Autodesk Fusion 360 part; units mm, degrees
(part 13 of 18)
  line L9909 (187.203, -152.492) -> (187.673, -152.838)
  line L9910 (135.949, -198.554) -> (136.521, -198.435)
  line L9911 (78.42, -213.805) -> (77.9903, -214.201)
  line L9912 (69.6987, -215.983) -> (70.2761, -216.122)
  line L9913 (67.7724, -199.389) -> (68.2951, -199.128)
  line L9914 (174.108, -155.66) -> (174.402, -155.154)
  line L9915 (135.386, -198.709) -> (135.949, -198.554)
  line L9916 (63.1589, -205.81) -> (63.2769, -205.237)
  line L9917 (81.1268, -207.35) -> (81.1251, -207.524)
  line L9918 (173.035, -159.571) -> (173.078, -158.988)
  line L9919 (173.277, -157.837) -> (173.432, -157.274)
  line L9920 (144.823, -213.382) -> (144.42, -213.805)
  line L9921 (142.711, -199.576) -> (143.203, -199.892)
  line L9922 (66.7829, -200.01) -> (67.2676, -199.684)
  line L9923 (81.0514, -206.184) -> (81.1079, -206.766)
  line L9924 (190.922, -161.862) -> (190.781, -162.429)
  line L9925 (147.027, -208.688) -> (146.922, -209.262)
  line L9926 (68.8336, -198.901) -> (69.3856, -198.709)
  line L9927 (190.602, -162.986) -> (190.389, -163.53)
  line L9928 (81.0121, -206.757) -> (80.9531, -206.166)
  line L9929 (78.8234, -213.382) -> (78.42, -213.805)
  line L9930 (186.561, -167.811) -> (186.044, -168.084)
  line L9931 (79.1986, -212.934) -> (78.8234, -213.382)
  line L9932 (145.199, -212.934) -> (144.823, -213.382)
  line L9933 (85.3443, -157.966) -> (85.2321, -158.549)
  line L9934 (182.85, -150.933) -> (183.43, -151.002)
  line L9935 (184.404, -168.696) -> (183.835, -168.828)
  line L9936 (69.2202, -215.937) -> (68.672, -215.735)
  line L9937 (177.268, -152.284) -> (177.772, -151.989)
  line L9938 (63.495, -204.792) -> (63.3443, -205.366)
  line L9939 (63.0612, -208.139) -> (63.0291, -207.555)
  line L9940 (63.9741, -211.163) -> (64.2446, -211.691)
  line L9941 (188.543, -153.618) -> (188.938, -154.049)
  line L9942 (132.32, -200.367) -> (132.783, -200.01)
  line L9943 (173.061, -160.739) -> (173.029, -160.155)
  line L9944 (79.6409, -202.381) -> (79.9457, -202.88)
  line L9945 (189.199, -165.534) -> (188.823, -165.982)
  line L9946 (65.9695, -200.801) -> (65.5489, -201.22)
  line L9947 (144.938, -201.449) -> (145.304, -201.904)
  line L9948 (69.5484, -198.759) -> (68.9847, -198.946)
  line L9949 (90.9847, -151.546) -> (90.4345, -151.769)
  line L9950 (63.541, -210.058) -> (63.7392, -210.617)
  line L9951 (67.5183, -215.058) -> (68.0392, -215.343)
  line L9952 (133.772, -199.389) -> (134.295, -199.128)
  line L9953 (63.7392, -210.617) -> (63.9741, -211.163)
  line L9954 (131.084, -201.606) -> (131.469, -201.166)
  line L9955 (187.99, -166.801) -> (187.536, -167.168)
  line L9956 (78.0223, -214.047) -> (78.453, -213.638)
  line L9957 (78.8557, -213.201) -> (79.2286, -212.739)
  line L9958 (179.78, -168.704) -> (179.22, -168.537)
  line L9959 (69.1318, -215.807) -> (69.6987, -215.983)
  line L9960 (173.562, -163.016) -> (173.382, -162.46)
  line L9961 (77.5654, -214.426) -> (78.0223, -214.047)
  line L9962 (76.4456, -199.533) -> (75.9179, -199.261)
  line L9963 (71.4521, -216.283) -> (72.0455, -216.305)
  line L9964 (63.2578, -208.905) -> (63.3803, -209.486)
  line L9965 (102.827, -157.638) -> (102.957, -158.208)
  line L9966 (97.1275, -151.43) -> (97.671, -151.644)
  line L9967 (100.121, -153.214) -> (100.543, -153.618)
  line L9968 (103.051, -158.784) -> (103.108, -159.366)
  line L9969 (98.7108, -152.176) -> (99.2028, -152.492)
  line L9970 (96.0047, -151.108) -> (96.5713, -151.251)
  line L9971 (103.127, -159.95) -> (103.125, -160.124)
  line L9972 (101.641, -154.981) -> (101.946, -155.48)
  line L9973 (101.946, -155.48) -> (102.218, -155.997)
  line L9974 (102.957, -158.208) -> (103.051, -158.784)
  line L9975 (103.108, -159.366) -> (103.127, -159.95)
  line L9976 (97.671, -151.644) -> (98.1995, -151.894)
  line L9977 (96.5713, -151.251) -> (97.1275, -151.43)
  line L9978 (100.543, -153.618) -> (100.938, -154.049)
  line L9979 (102.218, -155.997) -> (102.456, -156.531)
  line L9980 (103.095, -160.707) -> (103.027, -161.288)
  line L9981 (102.456, -156.531) -> (102.659, -157.078)
  line L9982 (101.304, -154.504) -> (101.641, -154.981)
  line L9983 (99.2028, -152.492) -> (99.6734, -152.838)
  line L9984 (103.125, -160.124) -> (103.095, -160.707)
  line L9985 (98.1995, -151.894) -> (98.7108, -152.176)
  line L9986 (102.659, -157.078) -> (102.827, -157.638)
  line L9987 (100.938, -154.049) -> (101.304, -154.504)
  line L9988 (99.6734, -152.838) -> (100.121, -153.214)
  line L9989 (146.153, -140.119) -> (146.391, -139.576)
  line L9990 (74.4039, -144.996) -> (73.8346, -145.128)
  line L9991 (22.539, -143.287) -> (23.0175, -143.639)
  line L9992 (63.1297, -136.625) -> (63.1742, -137.217)
  line L9993 (20.5495, -141.101) -> (20.8876, -141.589)
  line L9994 (36.7806, -138.729) -> (36.6024, -139.286)
  line L9995 (63.9088, -132.579) -> (63.6834, -133.129)
  line L9996 (23.1214, -143.823) -> (22.643, -143.487)
  line L9997 (76.1995, -128.194) -> (76.7108, -128.476)
  line L9998 (139.816, -145.034) -> (140.395, -144.9)
  line L9999 (79.5441, -141.363) -> (79.1986, -141.834)
  line L10000 (81.0318, -136.25) -> (81.0121, -135.657)
  line L10001 (87.0836, -154.206) -> (87.4688, -153.766)
  line L10002 (23.2676, -128.584) -> (23.7724, -128.289)
  line L10003 (30.3945, -144.9) -> (30.9627, -144.727)
  line L10004 (22.3203, -129.267) -> (22.7829, -128.91)
  line L10005 (37.0514, -135.084) -> (37.1079, -135.666)
  line L10006 (79.8006, -131.718) -> (79.4833, -131.217)
  line L10007 (75.671, -127.944) -> (76.1995, -128.194)
  line L10008 (35.3045, -130.804) -> (35.6409, -131.281)
  line L10009 (74.8143, -127.724) -> (74.2432, -127.561)
  line L10010 (63.0291, -136.455) -> (63.0332, -136.031)
  line L10011 (34.0223, -142.947) -> (34.453, -142.538)
  line L10012 (63.495, -133.692) -> (63.3443, -134.266)
  line L10013 (74.5713, -127.551) -> (75.1275, -127.73)
  line L10014 (140.963, -144.727) -> (141.518, -144.517)
  line L10015 (74.9627, -144.727) -> (75.5182, -144.517)
  line L10016 (33.6734, -129.138) -> (34.1207, -129.514)
  line L10017 (137.452, -145.183) -> (138.046, -145.205)
  line L10018 (29.2581, -145.223) -> (28.6766, -145.28)
  line L10019 (63.0332, -136.031) -> (63.0347, -135.871)
  line L10020 (36.3914, -139.576) -> (36.5935, -139.017)
  line L10021 (19.0612, -137.039) -> (19.0291, -136.455)
  line L10022 (85.1589, -158.41) -> (85.2769, -157.837)
  line L10023 (78.7525, -130.281) -> (78.3423, -129.852)
  line L10024 (86.7274, -154.669) -> (87.0836, -154.206)
  line L10025 (30.5713, -127.551) -> (31.1275, -127.73)
  line L10026 (25.1318, -144.707) -> (25.6987, -144.883)
  line L10027 (131.657, -142.493) -> (132.085, -142.905)
  line L10028 (68.672, -144.635) -> (68.138, -144.398)
  line L10029 (80.3914, -139.576) -> (80.5935, -139.017)
  line L10030 (72.0926, -145.3) -> (71.5085, -145.282)
  line L10031 (37.1251, -136.424) -> (37.0951, -137.007)
  line L10032 (80.8551, -134.48) -> (80.7185, -133.902)
  line L10033 (79.1334, -130.737) -> (78.7525, -130.281)
  line L10034 (26.5208, -127.335) -> (27.0994, -127.253)
  line L10035 (141.918, -128.161) -> (141.373, -127.924)
  line L10036 (73.6626, -127.437) -> (73.075, -127.351)
  line L10037 (69.5484, -127.659) -> (68.9847, -127.846)
  line L10038 (143.565, -143.326) -> (144.022, -142.947)
  line L10039 (65.9695, -153.401) -> (65.5489, -153.82)
  line L10040 (63.1245, -159.731) -> (63.1297, -160.325)
  line L10041 (136.123, -127.511) -> (135.548, -127.659)
  line L10042 (22.0847, -142.905) -> (22.539, -143.287)
  line L10043 (80.5935, -139.017) -> (80.7582, -138.447)
  line L10044 (79.8585, -140.87) -> (79.5441, -141.363)
  line L10045 (78.1207, -129.514) -> (78.5428, -129.918)
  line L10046 (129.683, -133.129) -> (129.495, -133.692)
  line L10047 (20.402, -131.454) -> (20.7274, -130.969)
  line L10048 (63.1587, -135.438) -> (63.1245, -136.031)
  line L10049 (64.5495, -141.101) -> (64.8876, -141.589)
  line L10050 (23.0175, -143.639) -> (23.5183, -143.958)
  line L10051 (64.9746, -141.859) -> (64.6274, -141.389)
  line L10052 (147.032, -136.25) -> (147.012, -135.657)
  line L10053 (25.2202, -144.837) -> (24.672, -144.635)
  line L10054 (145.801, -131.718) -> (145.483, -131.217)
  line L10055 (66.8893, -128.951) -> (66.417, -129.31)
  line L10056 (130.795, -131.037) -> (130.466, -131.531)
  line L10057 (24.8336, -127.801) -> (25.3856, -127.609)
  line L10058 (140.243, -127.561) -> (139.663, -127.437)
  line L10059 (34.8557, -142.101) -> (35.2286, -141.639)
  line L10060 (81.1268, -136.25) -> (81.1251, -136.424)
  line L10061 (77.9903, -143.101) -> (77.5358, -143.468)
  line L10062 (77.2028, -128.792) -> (77.6734, -129.138)
  line L10063 (130.17, -132.046) -> (129.909, -132.579)
  line L10064 (63.6834, -133.129) -> (63.495, -133.692)
  line L10065 (67.1214, -143.823) -> (66.643, -143.487)
  line L10066 (30.9634, -144.827) -> (30.4039, -144.996)
  line L10067 (136.276, -145.022) -> (136.861, -145.122)
  line L10068 (69.7803, -145.004) -> (69.2202, -144.837)
  line L10069 (19.3803, -138.386) -> (19.541, -138.958)
  line L10070 (66.0847, -142.905) -> (66.539, -143.287)
  line L10071 (19.3817, -138.76) -> (19.2379, -138.193)
  line L10072 (65.8816, -129.653) -> (66.3203, -129.267)
  line L10073 (72.0455, -145.205) -> (72.6391, -145.187)
  line L10074 (33.2028, -128.792) -> (33.6734, -129.138)
  line L10075 (75.9179, -151.861) -> (75.3734, -151.624)
  line L10076 (146.758, -138.447) -> (146.885, -137.867)
  line L10077 (81.0121, -135.657) -> (80.9531, -135.066)
  line L10078 (135.699, -144.883) -> (136.276, -145.022)
  line L10079 (31.5109, -144.623) -> (30.9634, -144.827)
  line L10080 (134.434, -128.069) -> (133.9, -128.329)
  line L10081 (63.1589, -134.71) -> (63.2769, -134.137)
  line L10082 (93.682, -150.909) -> (94.2663, -150.902)
  line L10083 (87.8816, -153.353) -> (88.3203, -152.967)
  line L10084 (20.0276, -140.387) -> (19.7774, -139.859)
  line L10085 (72.2663, -127.202) -> (72.8498, -127.233)
  line L10086 (133.518, -143.958) -> (134.039, -144.243)
  line L10087 (80.9575, -134.508) -> (81.0514, -135.084)
  line L10088 (36.8847, -137.867) -> (36.9725, -137.279)
  line L10089 (71.8893, -150.997) -> (71.2963, -151.029)
  line L10090 (143.084, -143.674) -> (143.565, -143.326)
  line L10091 (20.8876, -141.589) -> (21.2572, -142.054)
  line L10092 (35.57, -141.153) -> (35.8785, -140.646)
  line L10093 (73.8346, -145.128) -> (73.2581, -145.223)
  line L10094 (63.078, -135.288) -> (63.1589, -134.71)
  line L10095 (64.17, -132.046) -> (63.9088, -132.579)
  line L10096 (63.232, -134.849) -> (63.1587, -135.438)
  line L10097 (137.889, -127.297) -> (137.296, -127.329)
  line L10098 (147.012, -135.657) -> (146.953, -135.066)
  line L10099 (68.2951, -128.028) -> (68.8336, -127.801)
  line L10100 (25.9488, -127.454) -> (26.5208, -127.335)
  line L10101 (129.159, -135.438) -> (129.124, -136.031)
  line L10102 (70.5208, -127.335) -> (71.0994, -127.253)
  line L10103 (20.6274, -141.389) -> (20.3113, -140.898)
  line L10104 (19.5618, -139.316) -> (19.3817, -138.76)
  line L10105 (173.541, -162.658) -> (173.739, -163.217)
  line L10106 (65.157, -154.266) -> (64.7955, -154.737)
  line L10107 (28.0926, -145.3) -> (27.5085, -145.282)
  line L10108 (80.7185, -133.902) -> (80.5439, -133.335)
  line L10109 (72.8498, -127.233) -> (73.4301, -127.302)
  line L10110 (135.132, -144.707) -> (135.699, -144.883)
  line L10111 (85.6222, -156.722) -> (85.8482, -156.183)
  line L10112 (144.453, -142.538) -> (144.856, -142.101)
  line L10113 (89.7724, -151.989) -> (90.2951, -151.728)
  line L10114 (76.7108, -128.476) -> (77.2028, -128.792)
  line L10115 (134.039, -144.243) -> (134.578, -144.493)
  line L10116 (78.3423, -153.552) -> (77.9045, -153.151)
  line L10117 (36.4559, -132.831) -> (36.6591, -133.378)
  line L10118 (79.8006, -155.418) -> (79.4833, -154.917)
  line L10119 (77.4411, -129.079) -> (76.954, -128.74)
  line L10120 (88.3203, -152.967) -> (88.7829, -152.61)
  line L10121 (146.594, -139.017) -> (146.758, -138.447)
  line L10122 (32.0441, -144.384) -> (31.5109, -144.623)
  line L10123 (26.2761, -145.022) -> (26.8615, -145.122)
  line L10124 (34.42, -142.705) -> (33.9903, -143.101)
  line L10125 (80.6591, -133.378) -> (80.8266, -133.938)
  line L10126 (76.0441, -144.384) -> (75.5109, -144.623)
  line L10127 (95.4301, -151.002) -> (96.0047, -151.108)
  line L10128 (64.6274, -141.389) -> (64.3113, -140.898)
  line L10129 (29.8346, -145.128) -> (29.2581, -145.223)
  line L10130 (19.2578, -137.805) -> (19.3803, -138.386)
  line L10131 (78.7525, -153.981) -> (78.3423, -153.552)
  line L10132 (80.9531, -135.066) -> (80.8551, -134.48)
  line L10133 (29.2302, -145.13) -> (29.8162, -145.034)
  line L10134 (24.5778, -144.493) -> (25.1318, -144.707)
  line L10135 (65.7561, -142.727) -> (65.3513, -142.306)
  line L10136 (64.3113, -140.898) -> (64.0276, -140.387)
  line L10137 (69.5484, -151.359) -> (68.9847, -151.546)
  line L10138 (33.0587, -143.805) -> (32.5607, -144.111)
  line L10139 (64.7274, -130.969) -> (65.0836, -130.506)
  line L10140 (73.075, -151.051) -> (72.483, -151.004)
  line L10141 (146.972, -137.279) -> (147.021, -136.687)
  line L10142 (63.3817, -138.76) -> (63.2379, -138.193)
  line L10143 (86.1085, -155.66) -> (86.402, -155.154)
  line L10144 (91.3856, -151.309) -> (91.9488, -151.154)
  line L10145 (81.1251, -136.424) -> (81.0951, -137.007)
  line L10146 (70.7068, -127.4) -> (70.1233, -127.511)
  line L10147 (69.3856, -127.609) -> (69.9488, -127.454)
  line L10148 (36.6591, -133.378) -> (36.8266, -133.938)
  line L10149 (63.0612, -137.039) -> (63.0291, -136.455)
  line L10150 (34.453, -142.538) -> (34.8557, -142.101)
  line L10151 (21.7561, -142.727) -> (21.3513, -142.306)
  line L10152 (80.5439, -133.335) -> (80.3321, -132.78)
  line L10153 (141.518, -144.517) -> (142.059, -144.271)
  line L10154 (72.483, -127.304) -> (71.8893, -127.297)
  line L10155 (63.2769, -134.137) -> (63.4315, -133.574)
  line L10156 (78.42, -142.705) -> (77.9903, -143.101)
  line L10157 (65.157, -130.566) -> (64.7955, -131.037)
  line L10158 (63.6222, -133.022) -> (63.8482, -132.483)
  line L10159 (78.453, -142.538) -> (78.8557, -142.101)
  line L10160 (68.4345, -151.769) -> (67.9003, -152.029)
  line L10161 (63.541, -138.958) -> (63.7392, -139.517)
  line L10162 (77.6734, -129.138) -> (78.1207, -129.514)
  line L10163 (68.9847, -151.546) -> (68.4345, -151.769)
  line L10164 (132.539, -143.287) -> (133.018, -143.639)
  line L10165 (138.639, -145.187) -> (139.23, -145.13)
  line L10166 (74.2432, -151.261) -> (73.6626, -151.137)
  line L10167 (21.0836, -130.506) -> (21.4688, -130.066)
  line L10168 (22.7829, -128.91) -> (23.2676, -128.584)
  line L10169 (64.2446, -140.591) -> (64.5495, -141.101)
  line L10170 (80.7806, -138.729) -> (80.6024, -139.286)
  line L10171 (81.0514, -135.084) -> (81.1079, -135.666)
  line L10172 (137.296, -127.329) -> (136.707, -127.4)
  line L10173 (146.332, -132.78) -> (146.084, -132.24)
  line L10174 (70.1233, -151.211) -> (69.5484, -151.359)
  line L10175 (78.3423, -129.852) -> (77.9045, -129.451)
  line L10176 (142.581, -143.99) -> (143.084, -143.674)
  line L10177 (68.5778, -144.493) -> (69.1318, -144.707)
  line L10178 (70.7068, -151.1) -> (70.1233, -151.211)
  line L10179 (80.3887, -139.83) -> (80.1404, -140.359)
  line L10180 (36.5935, -139.017) -> (36.7582, -138.447)
  line L10181 (19.0347, -135.871) -> (19.078, -135.288)
  line L10182 (32.5607, -144.111) -> (32.0441, -144.384)
  line L10183 (80.2178, -132.297) -> (80.4559, -132.831)
  line L10184 (68.0392, -144.243) -> (68.5778, -144.493)
  line L10185 (25.3856, -127.609) -> (25.9488, -127.454)
  line L10186 (19.2379, -138.193) -> (19.1309, -137.619)
  line L10187 (68.8336, -127.801) -> (69.3856, -127.609)
  line L10188 (85.8482, -156.183) -> (86.1085, -155.66)
  line L10189 (63.0347, -135.871) -> (63.078, -135.288)
  line L10190 (21.4688, -130.066) -> (21.8816, -129.653)
  line L10191 (74.3945, -144.9) -> (74.9627, -144.727)
  line L10192 (142.059, -144.271) -> (142.581, -143.99)
  line L10193 (70.1233, -127.511) -> (69.5484, -127.659)
  line L10194 (75.1275, -127.73) -> (75.671, -127.944)
  line L10195 (19.2769, -134.137) -> (19.4315, -133.574)
  line L10196 (145.879, -140.646) -> (146.153, -140.119)
  line L10197 (63.1587, -159.138) -> (63.1245, -159.731)
  line L10198 (64.17, -155.746) -> (63.9088, -156.279)
  line L10199 (20.3113, -140.898) -> (20.0276, -140.387)
  line L10200 (64.402, -131.454) -> (64.7274, -130.969)
  line L10201 (79.6409, -131.281) -> (79.9457, -131.78)
  line L10202 (80.1404, -140.359) -> (79.8585, -140.87)
  line L10203 (145.133, -130.737) -> (144.753, -130.281)
  line L10204 (78.9379, -130.349) -> (79.3045, -130.804)
  line L10205 (138.046, -145.205) -> (138.639, -145.187)
  line L10206 (67.9003, -128.329) -> (67.3845, -128.623)
  line L10207 (37.0274, -137.588) -> (36.9224, -138.162)
  line L10208 (80.1527, -140.119) -> (80.3914, -139.576)
  line L10209 (73.6626, -151.137) -> (73.075, -151.051)
  line L10210 (73.2302, -145.13) -> (73.8162, -145.034)
  line L10211 (131.97, -129.701) -> (131.549, -130.12)
  line L10212 (81.1079, -135.666) -> (81.1268, -136.25)
  line L10213 (80.9224, -138.162) -> (80.7806, -138.729)
  line L10214 (23.5183, -143.958) -> (24.0392, -144.243)
  line L10215 (19.9741, -140.063) -> (20.2446, -140.591)
  line L10216 (65.6569, -142.493) -> (66.0847, -142.905)
  line L10217 (144.342, -129.852) -> (143.904, -129.451)
  line L10218 (64.1085, -131.96) -> (64.402, -131.454)
  line L10219 (71.682, -127.209) -> (72.2663, -127.202)
  line L10220 (132.417, -129.31) -> (131.97, -129.701)
  line L10221 (67.9003, -152.029) -> (67.3845, -152.323)
  line L10222 (23.6204, -144.127) -> (23.1214, -143.823)
  line L10223 (26.8615, -145.122) -> (27.4521, -145.183)
  line L10224 (87.4688, -153.766) -> (87.8816, -153.353)
  line L10225 (80.084, -132.24) -> (79.8006, -131.718)
  line L10226 (73.075, -127.351) -> (72.483, -127.304)
  line L10227 (67.7724, -128.289) -> (68.2951, -128.028)
  line L10228 (31.1275, -127.73) -> (31.671, -127.944)
  line L10229 (64.466, -155.231) -> (64.17, -155.746)
  line L10230 (80.7582, -138.447) -> (80.8847, -137.867)
  line L10231 (65.3513, -142.306) -> (64.9746, -141.859)
  line L10232 (63.5618, -139.316) -> (63.3817, -138.76)
  line L10233 (20.7274, -130.969) -> (21.0836, -130.506)
  line L10234 (20.9746, -141.859) -> (20.6274, -141.389)
  line L10235 (146.885, -137.867) -> (146.972, -137.279)
  line L10236 (74.2432, -127.561) -> (73.6626, -127.437)
  line L10237 (63.8482, -132.483) -> (64.1085, -131.96)
  line L10238 (142.954, -128.74) -> (142.446, -128.433)
  line L10239 (35.1986, -141.834) -> (34.8234, -142.282)
  line L10240 (36.3887, -139.83) -> (36.1404, -140.359)
  line L10241 (133.018, -143.639) -> (133.518, -143.958)
  line L10242 (75.9179, -128.161) -> (75.3734, -127.924)
  line L10243 (28.6391, -145.187) -> (29.2302, -145.13)
  line L10244 (80.4559, -132.831) -> (80.6591, -133.378)
  line L10245 (63.9088, -156.279) -> (63.6834, -156.829)
  line L10246 (146.855, -134.48) -> (146.719, -133.902)
  line L10247 (146.953, -135.066) -> (146.855, -134.48)
  line L10248 (79.1986, -141.834) -> (78.8234, -142.282)
  line L10249 (24.2951, -128.028) -> (24.8336, -127.801)
  line L10250 (144.753, -130.281) -> (144.342, -129.852)
  line L10251 (23.7724, -128.289) -> (24.2951, -128.028)
  line L10252 (78.0223, -142.947) -> (78.453, -142.538)
  line L10253 (146.544, -133.335) -> (146.332, -132.78)
  line L10254 (19.7774, -139.859) -> (19.5618, -139.316)
  line L10255 (85.078, -158.988) -> (85.1589, -158.41)
  line L10256 (78.8234, -142.282) -> (78.42, -142.705)
  line L10257 (19.7392, -139.517) -> (19.9741, -140.063)
  line L10258 (26.9269, -145.227) -> (26.35, -145.134)
  line L10259 (80.8266, -133.938) -> (80.9575, -134.508)
  line L10260 (66.3203, -129.267) -> (66.7829, -128.91)
  line L10261 (133.385, -128.623) -> (132.889, -128.951)
  line L10262 (31.671, -127.944) -> (32.1995, -128.194)
  line L10263 (79.2286, -141.639) -> (79.57, -141.153)
  line L10264 (19.0332, -136.031) -> (19.0347, -135.871)
  line L10265 (71.2963, -151.029) -> (70.7068, -151.1)
  line L10266 (88.7829, -152.61) -> (89.2676, -152.284)
  line L10267 (37.1079, -135.666) -> (37.1268, -136.25)
  line L10268 (19.1742, -137.217) -> (19.2578, -137.805)
  line L10269 (69.1318, -144.707) -> (69.6987, -144.883)
  line L10270 (80.3321, -132.78) -> (80.084, -132.24)
  line L10271 (79.4833, -154.917) -> (79.1334, -154.437)
  line L10272 (75.5109, -144.623) -> (74.9634, -144.827)
  line L10273 (32.0585, -144.271) -> (32.5813, -143.99)
  line L10274 (91.9488, -151.154) -> (92.5208, -151.035)
  line L10275 (131.257, -142.054) -> (131.657, -142.493)
  line L10276 (75.3734, -127.924) -> (74.8143, -127.724)
  line L10277 (68.4345, -128.069) -> (67.9003, -128.329)
  line L10278 (19.1589, -134.71) -> (19.2769, -134.137)
  line L10279 (78.8557, -142.101) -> (79.2286, -141.639)
  line L10280 (19.1309, -137.619) -> (19.0612, -137.039)
  line L10281 (76.5813, -143.99) -> (77.0844, -143.674)
  line L10282 (66.417, -153.01) -> (65.9695, -153.401)
  line L10283 (85.2769, -157.837) -> (85.4315, -157.274)
  line L10284 (20.2446, -140.591) -> (20.5495, -141.101)
  line L10285 (80.6024, -139.286) -> (80.3887, -139.83)
  line L10286 (90.2951, -151.728) -> (90.8336, -151.501)
  line L10287 (93.0994, -150.953) -> (93.682, -150.909)
  line L10288 (21.6569, -142.493) -> (22.0847, -142.905)
  line L10289 (35.6409, -131.281) -> (35.9457, -131.78)
  line L10290 (21.2572, -142.054) -> (21.6569, -142.493)
  line L10291 (79.57, -141.153) -> (79.8785, -140.646)
  line L10292 (63.1309, -137.619) -> (63.0612, -137.039)
  line L10293 (66.7829, -128.91) -> (67.2676, -128.584)
  line L10294 (67.3845, -128.623) -> (66.8893, -128.951)
  line L10295 (68.9847, -127.846) -> (68.4345, -128.069)
  line L10296 (66.417, -129.31) -> (65.9695, -129.701)
  line L10297 (36.8266, -133.938) -> (36.9575, -134.508)
  line L10298 (71.2963, -127.329) -> (70.7068, -127.4)
  line L10299 (71.5085, -145.282) -> (70.9269, -145.227)
  line L10300 (78.5428, -129.918) -> (78.9379, -130.349)
  line L10301 (63.1742, -137.217) -> (63.2578, -137.805)
  line L10302 (89.2676, -152.284) -> (89.7724, -151.989)
  line L10303 (145.229, -141.639) -> (145.57, -141.153)
  line L10304 (81.0274, -137.588) -> (80.9224, -138.162)
  line L10305 (64.0276, -140.387) -> (63.7774, -139.859)
  line L10306 (67.2676, -128.584) -> (67.7724, -128.289)
  line L10307 (79.3045, -130.804) -> (79.6409, -131.281)
  line L10308 (35.9457, -131.78) -> (36.2178, -132.297)
  line L10309 (25.6987, -144.883) -> (26.2761, -145.022)
  line L10310 (139.075, -127.351) -> (138.483, -127.304)
  line L10311 (134.985, -127.846) -> (134.434, -128.069)
  line L10312 (35.8785, -140.646) -> (36.1527, -140.119)
  line L10313 (74.9634, -144.827) -> (74.4039, -144.996)
  line L10314 (36.6024, -139.286) -> (36.3887, -139.83)
  line L10315 (34.1207, -129.514) -> (34.5428, -129.918)
  line L10316 (66.643, -143.487) -> (66.1873, -143.121)
  line L10317 (80.8847, -137.867) -> (80.9725, -137.279)
  line L10318 (144.856, -142.101) -> (145.229, -141.639)
  line L10319 (63.495, -157.392) -> (63.3443, -157.966)
  line L10320 (79.4833, -131.217) -> (79.1334, -130.737)
  line L10321 (67.3845, -152.323) -> (66.8893, -152.651)
  line L10322 (63.7774, -139.859) -> (63.5618, -139.316)
  line L10323 (139.23, -145.13) -> (139.816, -145.034)
  line L10324 (81.0951, -137.007) -> (81.0274, -137.588)
  line L10325 (69.9488, -127.454) -> (70.5208, -127.335)
  line L10326 (37.0211, -136.687) -> (37.0318, -136.25)
  line L10327 (129.13, -136.625) -> (129.174, -137.217)
  line L10328 (27.5085, -145.282) -> (26.9269, -145.227)
  line L10329 (66.8893, -152.651) -> (66.417, -153.01)
  line L10330 (64.7955, -131.037) -> (64.466, -131.531)
  line L10331 (133.9, -128.329) -> (133.385, -128.623)
  line L10332 (37.1268, -136.25) -> (37.1251, -136.424)
  line L10333 (72.6391, -145.187) -> (73.2302, -145.13)
  line L10334 (86.402, -155.154) -> (86.7274, -154.669)
  line L10335 (76.954, -128.74) -> (76.4456, -128.433)
  line L10336 (146.391, -139.576) -> (146.594, -139.017)
  line L10337 (27.0994, -127.253) -> (27.682, -127.209)
  line L10338 (145.483, -131.217) -> (145.133, -130.737)
  line L10339 (30.4039, -144.996) -> (29.8346, -145.128)
  line L10340 (67.0175, -143.639) -> (67.5183, -143.958)
  line L10341 (79.9457, -131.78) -> (80.2178, -132.297)
  line L10342 (129.232, -134.849) -> (129.159, -135.438)
  line L10343 (63.2578, -137.805) -> (63.3803, -138.386)
  line L10344 (75.3734, -151.624) -> (74.8143, -151.424)
  line L10345 (33.0844, -143.674) -> (33.5654, -143.326)
  line L10346 (90.8336, -151.501) -> (91.3856, -151.309)
  line L10347 (63.2379, -138.193) -> (63.1309, -137.619)
  line L10348 (35.5441, -141.363) -> (35.1986, -141.834)
  line L10349 (79.8785, -140.646) -> (80.1527, -140.119)
  line L10350 (143.441, -129.079) -> (142.954, -128.74)
  line L10351 (33.5654, -143.326) -> (34.0223, -142.947)
  line L10352 (94.8498, -150.933) -> (95.4301, -151.002)
  line L10353 (63.7392, -139.517) -> (63.9741, -140.063)
  line L10354 (141.373, -127.924) -> (140.814, -127.724)
  line L10355 (131.157, -130.566) -> (130.795, -131.037)
  line L10356 (146.719, -133.902) -> (146.544, -133.335)
  line L10357 (32.7108, -128.476) -> (33.2028, -128.792)
  line L10358 (77.5654, -143.326) -> (78.0223, -142.947)
  line L10359 (31.5182, -144.517) -> (32.0585, -144.271)
  line L10360 (63.3443, -157.966) -> (63.232, -158.549)
  line L10361 (36.2178, -132.297) -> (36.4559, -132.831)
  line L10362 (64.7955, -154.737) -> (64.466, -155.231)
  line L10363 (36.9224, -138.162) -> (36.7806, -138.729)
  line L10364 (24.0392, -144.243) -> (24.5778, -144.493)
  line L10365 (64.466, -131.531) -> (64.17, -132.046)
  line L10366 (72.483, -151.004) -> (71.8893, -150.997)
  line L10367 (27.682, -127.209) -> (28.2663, -127.202)
  line L10368 (28.0455, -145.205) -> (28.6391, -145.187)
  line L10369 (34.5428, -129.918) -> (34.9379, -130.349)
  line L10370 (79.1334, -154.437) -> (78.7525, -153.981)
  line L10371 (28.2663, -127.202) -> (28.8498, -127.233)
  line L10372 (66.539, -143.287) -> (67.0175, -143.639)
  line L10373 (71.0994, -127.253) -> (71.682, -127.209)
  line L10374 (70.2761, -145.022) -> (70.8615, -145.122)
  line L10375 (69.2202, -144.837) -> (68.672, -144.635)
  line L10376 (63.6834, -156.829) -> (63.495, -157.392)
  line L10377 (70.35, -145.134) -> (69.7803, -145.004)
  line L10378 (81.0211, -136.687) -> (81.0318, -136.25)
  line L10379 (65.5489, -130.12) -> (65.157, -130.566)
  line L10380 (32.1995, -128.194) -> (32.7108, -128.476)
  line L10381 (30.0047, -127.408) -> (30.5713, -127.551)
  line L10382 (29.8162, -145.034) -> (30.3945, -144.9)
  line L10383 (66.1873, -143.121) -> (65.7561, -142.727)
  line L10384 (24.672, -144.635) -> (24.138, -144.398)
  line L10385 (33.9903, -143.101) -> (33.5358, -143.468)
  line L10386 (77.5358, -143.468) -> (77.0587, -143.805)
  line L10387 (130.466, -131.531) -> (130.17, -132.046)
  line L10388 (19.8482, -132.483) -> (20.1085, -131.96)
  line L10389 (63.232, -158.549) -> (63.1587, -159.138)
  line L10390 (85.4315, -157.274) -> (85.6222, -156.722)
  line L10391 (63.1245, -136.031) -> (63.1297, -136.625)
  line L10392 (134.578, -144.493) -> (135.132, -144.707)
  line L10393 (68.138, -144.398) -> (67.6204, -144.127)
  line L10394 (26.35, -145.134) -> (25.7803, -145.004)
  line L10395 (36.1527, -140.119) -> (36.3914, -139.576)
  line L10396 (129.124, -136.031) -> (129.13, -136.625)
  line L10397 (71.8893, -127.297) -> (71.2963, -127.329)
  line L10398 (34.9379, -130.349) -> (35.3045, -130.804)
  line L10399 (138.483, -127.304) -> (137.889, -127.297)
  line L10400 (33.5358, -143.468) -> (33.0587, -143.805)
  line L10401 (77.9045, -153.151) -> (77.4411, -152.779)
  line L10402 (36.9575, -134.508) -> (37.0514, -135.084)
  line L10403 (22.643, -143.487) -> (22.1873, -143.121)
  line L10404 (32.5813, -143.99) -> (33.0844, -143.674)
  line L10405 (20.1085, -131.96) -> (20.402, -131.454)
  line L10406 (19.078, -135.288) -> (19.1589, -134.71)
  line L10407 (24.138, -144.398) -> (23.6204, -144.127)
  line L10408 (77.0844, -143.674) -> (77.5654, -143.326)
  line L10409 (136.707, -127.4) -> (136.123, -127.511)
  line L10410 (19.541, -138.958) -> (19.7392, -139.517)
  line L10411 (63.3803, -138.386) -> (63.541, -138.958)
  line L10412 (76.954, -152.44) -> (76.4456, -152.133)
  line L10413 (76.5607, -144.111) -> (76.0441, -144.384)
  line L10414 (80.084, -155.94) -> (79.8006, -155.418)
  line L10415 (143.904, -129.451) -> (143.441, -129.079)
  line L10416 (140.814, -127.724) -> (140.243, -127.561)
  line L10417 (70.9269, -145.227) -> (70.35, -145.134)
  line L10418 (69.6987, -144.883) -> (70.2761, -145.022)
  line L10419 (71.4521, -145.183) -> (72.0455, -145.205)
  line L10420 (28.6766, -145.28) -> (28.0926, -145.3)
  line L10421 (76.0585, -144.271) -> (76.5813, -143.99)
  line L10422 (22.1873, -143.121) -> (21.7561, -142.727)
  line L10423 (28.8498, -127.233) -> (29.4301, -127.302)
  line L10424 (36.9725, -137.279) -> (37.0211, -136.687)
  line L10425 (132.889, -128.951) -> (132.417, -129.31)
  line L10426 (70.8615, -145.122) -> (71.4521, -145.183)
  line L10427 (136.861, -145.122) -> (137.452, -145.183)
  line L10428 (63.3443, -134.266) -> (63.232, -134.849)
  line L10429 (65.9695, -129.701) -> (65.5489, -130.12)
  line L10430 (146.084, -132.24) -> (145.801, -131.718)
  line L10431 (63.9741, -140.063) -> (64.2446, -140.591)
  line L10432 (92.5208, -151.035) -> (93.0994, -150.953)
  line L10433 (132.085, -142.905) -> (132.539, -143.287)
  line L10434 (65.5489, -153.82) -> (65.157, -154.266)
  line L10435 (135.548, -127.659) -> (134.985, -127.846)
  line L10436 (75.5182, -144.517) -> (76.0585, -144.271)
  line L10437 (131.549, -130.12) -> (131.157, -130.566)
  line L10438 (77.0587, -143.805) -> (76.5607, -144.111)
  line L10439 (27.4521, -145.183) -> (28.0455, -145.205)
  line L10440 (129.344, -134.266) -> (129.232, -134.849)
  line L10441 (76.4456, -152.133) -> (75.9179, -151.861)
  line L10442 (19.0291, -136.455) -> (19.0332, -136.031)
  line L10443 (25.7803, -145.004) -> (25.2202, -144.837)
  line L10444 (147.021, -136.687) -> (147.032, -136.25)
  line L10445 (76.4456, -128.433) -> (75.9179, -128.161)
  line L10446 (145.57, -141.153) -> (145.879, -140.646)
  line L10447 (67.5183, -143.958) -> (68.0392, -144.243)
  line L10448 (29.4301, -127.302) -> (30.0047, -127.408)
  line L10449 (74.0047, -127.408) -> (74.5713, -127.551)
  line L10450 (73.8162, -145.034) -> (74.3945, -144.9)
  line L10451 (129.495, -133.692) -> (129.344, -134.266)
  line L10452 (77.4411, -152.779) -> (76.954, -152.44)
  line L10453 (74.8143, -151.424) -> (74.2432, -151.261)
  line L10454 (73.2581, -145.223) -> (72.6766, -145.28)
  line L10455 (63.1297, -160.325) -> (63.1742, -160.917)
  line L10456 (30.9627, -144.727) -> (31.5182, -144.517)
  line L10457 (139.663, -127.437) -> (139.075, -127.351)
  line L10458 (65.4688, -130.066) -> (65.8816, -129.653)
  line L10459 (35.8585, -140.87) -> (35.5441, -141.363)
  line L10460 (37.0951, -137.007) -> (37.0274, -137.588)
  line L10461 (21.3513, -142.306) -> (20.9746, -141.859)
  line L10462 (63.4315, -133.574) -> (63.6222, -133.022)
  line L10463 (72.6766, -145.28) -> (72.0926, -145.3)
  line L10464 (34.8234, -142.282) -> (34.42, -142.705)
  line L10465 (65.0836, -130.506) -> (65.4688, -130.066)
  line L10466 (36.1404, -140.359) -> (35.8585, -140.87)
  line L10467 (19.4315, -133.574) -> (19.6222, -133.022)
  line L10468 (65.2572, -142.054) -> (65.6569, -142.493)
  line L10469 (64.8876, -141.589) -> (65.2572, -142.054)
  line L10470 (19.6222, -133.022) -> (19.8482, -132.483)
  line L10471 (73.4301, -127.302) -> (74.0047, -127.408)
  line L10472 (35.2286, -141.639) -> (35.57, -141.153)
  line L10473 (80.9725, -137.279) -> (81.0211, -136.687)
  line L10474 (21.8816, -129.653) -> (22.3203, -129.267)
  line L10475 (129.909, -132.579) -> (129.683, -133.129)
  line L10476 (94.2663, -150.902) -> (94.8498, -150.933)
  line L10477 (77.9045, -129.451) -> (77.4411, -129.079)
  line L10478 (67.6204, -144.127) -> (67.1214, -143.823)
  line L10479 (142.446, -128.433) -> (141.918, -128.161)
  line L10480 (140.395, -144.9) -> (140.963, -144.727)
  line L10481 (144.022, -142.947) -> (144.453, -142.538)
  line L10482 (36.7582, -138.447) -> (36.8847, -137.867)
  line L10483 (100.856, -165.801) -> (101.229, -165.339)
  line L10484 (85.9741, -163.763) -> (86.2446, -164.291)
  line L10485 (102.389, -163.53) -> (102.14, -164.059)
  line L10486 (86.6274, -165.089) -> (86.3113, -164.598)
  line L10487 (101.57, -164.853) -> (101.879, -164.346)
  line L10488 (92.2761, -168.722) -> (92.8615, -168.822)
  line L10489 (85.3803, -162.086) -> (85.541, -162.658)
  line L10490 (96.3945, -168.6) -> (96.9627, -168.427)
  line L10491 (97.5182, -168.217) -> (98.0585, -167.971)
  line L10492 (87.6569, -166.193) -> (88.0847, -166.605)
  line L10493 (95.8162, -168.734) -> (96.3945, -168.6)
  line L10494 (86.2446, -164.291) -> (86.5495, -164.801)
  line L10495 (101.879, -164.346) -> (102.153, -163.819)
  line L10496 (86.3113, -164.598) -> (86.0276, -164.087)
  line L10497 (86.0276, -164.087) -> (85.7774, -163.559)
  line L10498 (101.229, -165.339) -> (101.57, -164.853)
  line L10499 (101.544, -165.063) -> (101.199, -165.534)
  line L10500 (90.0392, -167.943) -> (90.5778, -168.193)
  line L10501 (88.0847, -166.605) -> (88.539, -166.987)
  line L10502 (85.5618, -163.016) -> (85.3817, -162.46)
  line L10503 (88.643, -167.187) -> (88.1873, -166.821)
  line L10504 (85.0332, -159.731) -> (85.0347, -159.571)
  line L10505 (86.8876, -165.289) -> (87.2572, -165.754)
  line L10506 (89.6204, -167.827) -> (89.1214, -167.523)
  line L10507 (102.14, -164.059) -> (101.858, -164.57)
  line L10508 (103.021, -160.387) -> (103.032, -159.95)
  line L10509 (95.2302, -168.83) -> (95.8162, -168.734)
  line L10510 (90.138, -168.098) -> (89.6204, -167.827)
  line L10511 (91.7803, -168.704) -> (91.2202, -168.537)
  line L10512 (100.453, -166.238) -> (100.856, -165.801)
  line L10513 (102.885, -161.567) -> (102.972, -160.979)
  line L10514 (99.0844, -167.374) -> (99.5654, -167.026)
  line L10515 (92.8615, -168.822) -> (93.4521, -168.883)
  line L10516 (102.758, -162.147) -> (102.885, -161.567)
  line L10517 (102.153, -163.819) -> (102.391, -163.276)
  line L10518 (103.027, -161.288) -> (102.922, -161.862)
  line L10519 (85.7392, -163.217) -> (85.9741, -163.763)
  line L10520 (87.7561, -166.427) -> (87.3513, -166.006)
  line L10521 (100.022, -166.647) -> (100.453, -166.238)
  line L10522 (85.7774, -163.559) -> (85.5618, -163.016)
  line L10523 (85.2379, -161.893) -> (85.1309, -161.319)
  line L10524 (87.2572, -165.754) -> (87.6569, -166.193)
  line L10525 (102.594, -162.717) -> (102.758, -162.147)
  line L10526 (89.5183, -167.658) -> (90.0392, -167.943)
  line L10527 (96.9627, -168.427) -> (97.5182, -168.217)
  line L10528 (100.823, -165.982) -> (100.42, -166.405)
  line L10529 (90.672, -168.335) -> (90.138, -168.098)
  line L10530 (85.1742, -160.917) -> (85.2578, -161.505)
  line L10531 (97.5109, -168.323) -> (96.9634, -168.527)
  line L10532 (103.032, -159.95) -> (103.012, -159.357)
  line L10533 (91.6987, -168.583) -> (92.2761, -168.722)
  line L10534 (91.1318, -168.407) -> (91.6987, -168.583)
  line L10535 (94.6391, -168.887) -> (95.2302, -168.83)
  line L10536 (99.9903, -166.801) -> (99.5358, -167.168)
  line L10537 (85.0612, -160.739) -> (85.0291, -160.155)
  line L10538 (100.42, -166.405) -> (99.9903, -166.801)
  line L10539 (94.0926, -169) -> (93.5085, -168.982)
  line L10540 (102.781, -162.429) -> (102.602, -162.986)
  line L10541 (92.9269, -168.927) -> (92.35, -168.834)
  line L10542 (93.5085, -168.982) -> (92.9269, -168.927)
  line L10543 (89.1214, -167.523) -> (88.643, -167.187)
  line L10544 (85.0347, -159.571) -> (85.078, -158.988)
  line L10545 (102.972, -160.979) -> (103.021, -160.387)
  line L10546 (99.0587, -167.505) -> (98.5607, -167.811)
  line L10547 (99.5358, -167.168) -> (99.0587, -167.505)
  line L10548 (96.4039, -168.696) -> (95.8346, -168.828)
  line L10549 (99.5654, -167.026) -> (100.022, -166.647)
  line L10550 (86.5495, -164.801) -> (86.8876, -165.289)
  line L10551 (94.6766, -168.98) -> (94.0926, -169)
  line L10552 (85.3817, -162.46) -> (85.2379, -161.893)
  line L10553 (85.541, -162.658) -> (85.7392, -163.217)
  line L10554 (93.4521, -168.883) -> (94.0455, -168.905)
  line L10555 (102.391, -163.276) -> (102.594, -162.717)
  line L10556 (102.922, -161.862) -> (102.781, -162.429)
  line L10557 (96.9634, -168.527) -> (96.4039, -168.696)
  line L10558 (101.858, -164.57) -> (101.544, -165.063)
  line L10559 (88.539, -166.987) -> (89.0175, -167.339)
  line L10560 (98.0441, -168.084) -> (97.5109, -168.323)
  line L10561 (86.9746, -165.559) -> (86.6274, -165.089)
  line L10562 (98.5813, -167.69) -> (99.0844, -167.374)
  line L10563 (85.1309, -161.319) -> (85.0612, -160.739)
  line L10564 (90.5778, -168.193) -> (91.1318, -168.407)
  line L10565 (94.0455, -168.905) -> (94.6391, -168.887)
  line L10566 (88.1873, -166.821) -> (87.7561, -166.427)
  line L10567 (92.35, -168.834) -> (91.7803, -168.704)
  line L10568 (89.0175, -167.339) -> (89.5183, -167.658)
  line L10569 (98.5607, -167.811) -> (98.0441, -168.084)
  line L10570 (87.3513, -166.006) -> (86.9746, -165.559)
  line L10571 (91.2202, -168.537) -> (90.672, -168.335)
  line L10572 (101.199, -165.534) -> (100.823, -165.982)
  line L10573 (85.0291, -160.155) -> (85.0332, -159.731)
  line L10574 (85.2578, -161.505) -> (85.3803, -162.086)
  line L10575 (95.2581, -168.923) -> (94.6766, -168.98)
  line L10576 (95.8346, -168.828) -> (95.2581, -168.923)
  line L10577 (98.0585, -167.971) -> (98.5813, -167.69)
  line L10578 (102.602, -162.986) -> (102.389, -163.53)
  line L10579 (101.483, -154.917) -> (101.133, -154.437)
  line L10580 (95.6626, -151.137) -> (95.075, -151.051)
  line L10581 (101.133, -154.437) -> (100.753, -153.981)
  line L10582 (102.084, -155.94) -> (101.801, -155.418)
  line L10583 (97.3734, -151.624) -> (96.8143, -151.424)
  line L10584 (98.4456, -152.133) -> (97.9179, -151.861)
  line L10585 (102.953, -158.766) -> (102.855, -158.18)
  line L10586 (99.4411, -152.779) -> (98.954, -152.44)
  line L10587 (100.753, -153.981) -> (100.342, -153.552)
  line L10588 (94.483, -151.004) -> (93.8893, -150.997)
  line L10589 (102.719, -157.602) -> (102.544, -157.035)
  line L10590 (99.9045, -153.151) -> (99.4411, -152.779)
  line L10591 (102.332, -156.48) -> (102.084, -155.94)
  line L10592 (93.8893, -150.997) -> (93.2963, -151.029)
  line L10593 (97.9179, -151.861) -> (97.3734, -151.624)
  line L10594 (93.2963, -151.029) -> (92.7068, -151.1)
  line L10595 (95.075, -151.051) -> (94.483, -151.004)
  line L10596 (101.801, -155.418) -> (101.483, -154.917)
  line L10597 (98.954, -152.44) -> (98.4456, -152.133)
  line L10598 (100.342, -153.552) -> (99.9045, -153.151)
  line L10599 (102.855, -158.18) -> (102.719, -157.602)
  line L10600 (103.012, -159.357) -> (102.953, -158.766)
  line L10601 (96.8143, -151.424) -> (96.2432, -151.261)
  line L10602 (102.544, -157.035) -> (102.332, -156.48)
  line L10603 (96.2432, -151.261) -> (95.6626, -151.137)
  line L10604 (129.562, -139.316) -> (129.382, -138.76)
  line L10605 (129.029, -136.455) -> (129.033, -136.031)
  line L10606 (135.22, -144.837) -> (134.672, -144.635)
  line L10607 (129.131, -137.619) -> (129.061, -137.039)
  line L10608 (133.62, -144.127) -> (133.121, -143.823)
  line L10609 (129.174, -137.217) -> (129.258, -137.805)
  line L10610 (136.927, -145.227) -> (136.35, -145.134)
  line L10611 (133.121, -143.823) -> (132.643, -143.487)
  line L10612 (130.245, -140.591) -> (130.55, -141.101)
  line L10613 (129.238, -138.193) -> (129.131, -137.619)
  line L10614 (129.739, -139.517) -> (129.974, -140.063)
  line L10615 (132.643, -143.487) -> (132.187, -143.121)
  line L10616 (129.38, -138.386) -> (129.541, -138.958)
  line L10617 (129.974, -140.063) -> (130.245, -140.591)
  line L10618 (129.777, -139.859) -> (129.562, -139.316)
  line L10619 (134.672, -144.635) -> (134.138, -144.398)
  line L10620 (138.677, -145.28) -> (138.093, -145.3)
  line L10621 (130.028, -140.387) -> (129.777, -139.859)
  line L10622 (134.138, -144.398) -> (133.62, -144.127)
  line L10623 (132.187, -143.121) -> (131.756, -142.727)
  line L10624 (131.756, -142.727) -> (131.351, -142.306)
  line L10625 (140.404, -144.996) -> (139.835, -145.128)
  line L10626 (130.975, -141.859) -> (130.627, -141.389)
  line L10627 (130.627, -141.389) -> (130.311, -140.898)
  line L10628 (136.35, -145.134) -> (135.78, -145.004)
  line L10629 (129.258, -137.805) -> (129.38, -138.386)
  line L10630 (137.509, -145.282) -> (136.927, -145.227)
  line L10631 (139.258, -145.223) -> (138.677, -145.28)
  line L10632 (129.035, -135.871) -> (129.078, -135.288)
  line L10633 (129.061, -137.039) -> (129.029, -136.455)
  line L10634 (138.093, -145.3) -> (137.509, -145.282)
  line L10635 (129.541, -138.958) -> (129.739, -139.517)
  line L10636 (139.835, -145.128) -> (139.258, -145.223)
  line L10637 (129.033, -136.031) -> (129.035, -135.871)
  line L10638 (135.78, -145.004) -> (135.22, -144.837)
  line L10639 (130.311, -140.898) -> (130.028, -140.387)
  line L10640 (131.351, -142.306) -> (130.975, -141.859)
  line L10641 (140.963, -144.827) -> (140.404, -144.996)
  line L10642 (129.382, -138.76) -> (129.238, -138.193)
  line L10643 (130.55, -141.101) -> (130.888, -141.589)
  line L10644 (130.888, -141.589) -> (131.257, -142.054)
  line L10645 (123.858, -93.4704) -> (123.544, -93.963)
  line L10646 (124.781, -91.3293) -> (124.602, -91.8858)
  line L10647 (125.095, -89.6073) -> (125.027, -90.1877)
  line L10648 (124.602, -91.8858) -> (124.389, -92.4297)
  line L10649 (124.14, -92.9586) -> (123.858, -93.4704)
  line L10650 (123.544, -93.963) -> (123.199, -94.4342)
  line L10651 (124.389, -92.4297) -> (124.14, -92.9586)
  line L10652 (123.199, -94.4342) -> (122.823, -94.8821)
  line L10653 (124.922, -90.7625) -> (124.781, -91.3293)
  line L10654 (125.027, -90.1877) -> (124.922, -90.7625)
  line L10655 (160.093, -216.4) -> (159.509, -216.382)
  line L10656 (181.889, -127.297) -> (181.296, -127.329)
  line L10657 (156.295, -199.128) -> (156.834, -198.901)
  line L10658 (190.953, -135.066) -> (190.855, -134.48)
  line L10659 (151.078, -206.388) -> (151.159, -205.81)
  line L10660 (177.62, -144.127) -> (177.121, -143.823)
  line L10661 (161.258, -216.323) -> (160.677, -216.38)
  line L10662 (182.093, -145.3) -> (181.509, -145.282)
  line L10663 (189.133, -130.737) -> (188.753, -130.281)
  line L10664 (191.125, -136.424) -> (191.095, -137.007)
  line L10665 (178.039, -167.943) -> (178.578, -168.193)
  line L10666 (165.99, -214.201) -> (165.536, -214.568)
  line L10667 (166.42, -213.805) -> (165.99, -214.201)
  line L10668 (175.351, -142.306) -> (174.975, -141.859)
  line L10669 (176.643, -143.487) -> (176.187, -143.121)
  line L10670 (190.758, -138.447) -> (190.885, -137.867)
  line L10671 (167.199, -212.934) -> (166.823, -213.382)
  line L10672 (166.823, -213.382) -> (166.42, -213.805)
  line L10673 (165.536, -214.568) -> (165.059, -214.905)
  line L10674 (152.975, -212.959) -> (152.627, -212.489)
  line L10675 (107.078, -111.588) -> (107.159, -111.01)
  line L10676 (185.511, -144.623) -> (184.963, -144.827)
  line L10677 (181.296, -127.329) -> (180.707, -127.4)
  line L10678 (169.127, -207.35) -> (169.125, -207.524)
  line L10679 (189.483, -131.217) -> (189.133, -130.737)
  line L10680 (155.268, -199.684) -> (155.772, -199.389)
  line L10681 (174.311, -140.898) -> (174.028, -140.387)
  line L10682 (162.404, -216.096) -> (161.835, -216.228)
  line L10683 (179.132, -168.407) -> (179.699, -168.583)
  line L10684 (169.108, -206.766) -> (169.127, -207.35)
  line L10685 (178.672, -144.635) -> (178.138, -144.398)
  line L10686 (157.386, -198.709) -> (157.949, -198.554)
  line L10687 (173.739, -163.217) -> (173.974, -163.763)
  line L10688 (168.957, -205.608) -> (169.051, -206.184)
  line L10689 (190.953, -158.766) -> (190.855, -158.18)
  line L10690 (169.051, -206.184) -> (169.108, -206.766)
  line L10691 (169.125, -207.524) -> (169.095, -208.107)
  line L10692 (160.677, -216.38) -> (160.093, -216.4)
  line L10693 (156.834, -198.901) -> (157.386, -198.709)
  line L10694 (183.663, -127.437) -> (183.075, -127.351)
  line L10695 (182.483, -127.304) -> (181.889, -127.297)
  line L10696 (181.452, -168.883) -> (182.046, -168.905)
  line L10697 (180.707, -127.4) -> (180.123, -127.511)
  line L10698 (161.835, -216.228) -> (161.258, -216.323)
  line L10699 (183.075, -127.351) -> (182.483, -127.304)
  line L10700 (191.032, -159.95) -> (191.012, -159.357)
  line L10701 (164.711, -199.576) -> (165.203, -199.892)
  line L10702 (180.35, -145.134) -> (179.78, -145.004)
  line L10703 (178.578, -168.193) -> (179.132, -168.407)
  line L10704 (156.138, -215.498) -> (155.62, -215.227)
  line L10705 (155.772, -199.389) -> (156.295, -199.128)
  line L10706 (153.351, -213.406) -> (152.975, -212.959)
  line L10707 (151.432, -204.674) -> (151.622, -204.122)
  line L10708 (151.562, -210.416) -> (151.382, -209.86)
  line L10709 (152.028, -211.487) -> (151.777, -210.959)
  line L10710 (151.382, -209.86) -> (151.238, -209.293)
  line L10711 (152.311, -211.998) -> (152.028, -211.487)
  line L10712 (190.391, -139.576) -> (190.594, -139.017)
  line L10713 (191.012, -159.357) -> (190.953, -158.766)
  line L10714 (179.699, -168.583) -> (180.276, -168.722)
  line L10715 (165.203, -199.892) -> (165.673, -200.238)
  line L10716 (156.672, -215.735) -> (156.138, -215.498)
  line L10717 (165.673, -200.238) -> (166.121, -200.614)
  line L10718 (183.835, -145.128) -> (183.258, -145.223)
  line L10719 (178.578, -144.493) -> (179.132, -144.707)
  line L10720 (151.277, -205.237) -> (151.432, -204.674)
  line L10721 (190.594, -139.017) -> (190.758, -138.447)
  line L10722 (164.199, -199.294) -> (164.711, -199.576)
  line L10723 (163.671, -199.044) -> (164.199, -199.294)
  line L10724 (175.756, -142.727) -> (175.351, -142.306)
  line L10725 (107.159, -111.01) -> (107.277, -110.437)
  line L10726 (153.257, -213.154) -> (153.657, -213.593)
  line L10727 (180.276, -168.722) -> (180.861, -168.822)
  line L10728 (155.62, -215.227) -> (155.121, -214.923)
  line L10729 (154.643, -214.587) -> (154.187, -214.221)
  line L10730 (155.121, -214.923) -> (154.643, -214.587)
  line L10731 (151.159, -205.81) -> (151.277, -205.237)
  line L10732 (190.885, -161.567) -> (190.972, -160.979)
  line L10733 (151.38, -209.486) -> (151.541, -210.058)
  line L10734 (184.814, -127.724) -> (184.243, -127.561)
  line L10735 (182.639, -145.187) -> (183.23, -145.13)
  line L10736 (190.972, -160.979) -> (191.021, -160.387)
  line L10737 (153.657, -213.593) -> (154.085, -214.005)
  line L10738 (157.78, -216.104) -> (157.22, -215.937)
  line L10739 (188.453, -142.538) -> (188.856, -142.101)
  line L10740 (188.42, -142.705) -> (187.99, -143.101)
  line L10741 (173.38, -138.386) -> (173.541, -138.958)
  line L10742 (120.711, -104.776) -> (121.203, -105.092)
  line L10743 (113.386, -103.909) -> (113.949, -103.754)
  line L10744 (174.795, -131.037) -> (174.466, -131.531)
  line L10745 (20.17, -132.046) -> (19.9088, -132.579)
  line L10746 (36.9531, -135.066) -> (36.8551, -134.48)
  line L10747 (37.0121, -135.657) -> (36.9531, -135.066)
  line L10748 (187.203, -128.792) -> (187.673, -129.138)
  line L10749 (165.059, -214.905) -> (164.561, -215.211)
  line L10750 (189.801, -131.718) -> (189.483, -131.217)
  line L10751 (185.518, -144.517) -> (186.059, -144.271)
  line L10752 (190.153, -140.119) -> (190.391, -139.576)
  line L10753 (21.157, -130.566) -> (20.7955, -131.037)
  line L10754 (186.044, -144.384) -> (185.511, -144.623)
  line L10755 (19.1245, -136.031) -> (19.1297, -136.625)
  line L10756 (173.174, -137.217) -> (173.258, -137.805)
  line L10757 (175.97, -129.701) -> (175.549, -130.12)
  line L10758 (157.22, -215.937) -> (156.672, -215.735)
  line L10759 (178.985, -127.846) -> (178.434, -128.069)
  line L10760 (151.174, -208.317) -> (151.258, -208.905)
  line L10761 (187.084, -167.374) -> (187.565, -167.026)
  line L10762 (158.35, -216.234) -> (157.78, -216.104)
  line L10763 (180.861, -168.822) -> (181.452, -168.883)
  line L10764 (190.855, -158.18) -> (190.719, -157.602)
  line L10765 (151.035, -206.971) -> (151.078, -206.388)
  line L10766 (187.904, -129.451) -> (187.441, -129.079)
  line L10767 (33.4411, -129.079) -> (32.954, -128.74)
  line L10768 (191.021, -136.687) -> (191.032, -136.25)
  line L10769 (191.108, -135.666) -> (191.127, -136.25)
  line L10770 (179.699, -144.883) -> (180.276, -145.022)
  line L10771 (118.005, -103.708) -> (118.571, -103.851)
  line L10772 (28.483, -127.304) -> (27.8893, -127.297)
  line L10773 (107.432, -109.874) -> (107.622, -109.322)
  line L10774 (188.453, -166.238) -> (188.856, -165.801)
  line L10775 (152.627, -212.489) -> (152.311, -211.998)
  line L10776 (190.972, -137.279) -> (191.021, -136.687)
  line L10777 (173.974, -140.063) -> (174.245, -140.591)
  line L10778 (27.8893, -127.297) -> (27.2963, -127.329)
  line L10779 (20.466, -131.531) -> (20.17, -132.046)
  line L10780 (33.9045, -129.451) -> (33.4411, -129.079)
  line L10781 (189.879, -164.346) -> (190.153, -163.819)
  line L10782 (32.954, -128.74) -> (32.4456, -128.433)
  line L10783 (191.127, -136.25) -> (191.125, -136.424)
  line L10784 (190.781, -138.729) -> (190.602, -139.286)
  line L10785 (187.673, -129.138) -> (188.121, -129.514)
  line L10786 (173.541, -138.958) -> (173.739, -139.517)
  line L10787 (107.277, -110.437) -> (107.432, -109.874)
  line L10788 (151.777, -210.959) -> (151.562, -210.416)
  line L10789 (25.5484, -127.659) -> (24.9847, -127.846)
  line L10790 (159.509, -216.382) -> (158.927, -216.327)
  line L10791 (190.602, -139.286) -> (190.389, -139.83)
  line L10792 (151.258, -208.905) -> (151.38, -209.486)